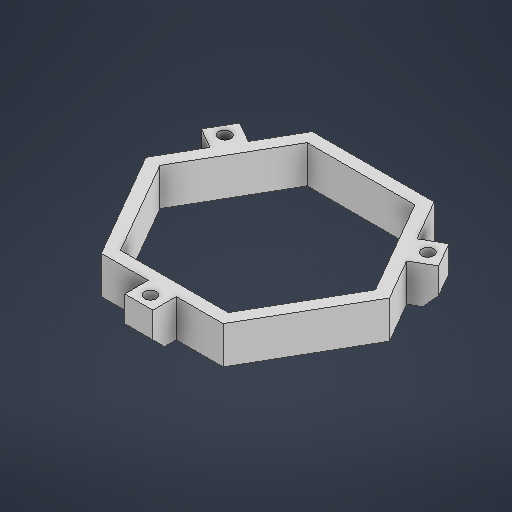
# Autodesk Inventor part: Gear Base
Saved by Autodesk Inventor 2026.3 (Build 303398000, 398)
## iProperties
Created: 2026-06-26
Part Number: Gear Base
Material: Generic
Document SubType Name: Modeling
Designer: joaqu
Density: 1 g/cm^3
Appearance: Default
Author: joaqu
Autodesk Inventor part; units mm, degrees
ref_plane "YZ Plane" through (0, 0, 0) normal (1, 0, 0) x (0, 1, 0)
ref_plane "XZ Plane" through (0, 0, 0) normal (0, 1, 0) x (-1, 0, 0)
ref_plane "XY Plane" through (0, 0, 0) normal (0, 0, 1) x (1, 0, 0)
sketch "Sketch1" plane through (0, 0, 0) normal (0, 1, 0) x (-1, 0, 0)
  line L0 (-115, 0) -> (-57.5, 99.5929)
  line L1 (-57.5, 99.5929) -> (57.5, 99.5929)
  line L2 (57.5, 99.5929) -> (115, 0)
  line L3 (115, 0) -> (57.5, -99.5929)
  line L4 (57.5, -99.5929) -> (-57.5, -99.5929)
  line L5 (-57.5, -99.5929) -> (-115, 0)
  line L6 (-130, 0) -> (-65, 112.5833)
  line L7 (-65, 112.5833) -> (65, 112.5833)
  line L8 (65, 112.5833) -> (130, 0)
  line L9 (130, 0) -> (65, -112.5833)
  line L10 (65, -112.5833) -> (-65, -112.5833)
  line L11 (-65, -112.5833) -> (-130, 0)
  point P0 (0, 0)
  point P1 (0, 0)
  point P2 (0, 0)
  dimension "d0" = 115
  dimension "d2" = 130
  constraints: 24 end point, 2 coincident, 26 other
  measures "d0" distance of L3.end L4.end
  measures "d2" distance of L9.end L10.end
extrude "Extrusion1" add sketch "Sketch1" along normal blind 40
sketch "Sketch3" plane through (-65, 0, 112.5833) normal (0, 0, 1) x (1, 0, 0)
  line L0 (130, 0) -> (0, 0) projected
  line L1 (130, 40) -> (0, 40) projected
  line L2 (50, 0) -> (80, 0)
  line L3 (80, 0) -> (80, 40)
  line L4 (80, 40) -> (50, 40)
  line L5 (50, 40) -> (50, 0)
  point P0 (65, 0)
  point P1 (65, 0)
  point P2 (65, 0)
  dimension "d5" = 15
  dimension "d6" = 15
  constraints: 8 end point, 2 midpoint, 2 parallel, 2 point on line, 1 horizontal, 1 perpendicular
  measures "d5" distance from line of L5 point (65, 0)
  measures "d6" distance from line of L3 point (65, 0)
extrude "Extrusion2" add sketch "Sketch3" along normal blind 25
chamfer "Chamfer1" distance 12.5 angle 45 1 edges at (0, 0, 137.5833)
sketch "Sketch4" plane through (-15, 12.5, 137.5833) normal (0, -0.7071, 0.7071) x (1, 0, 0)
  circle A0 centre (15, -8.8387) radius 6.375
  line L0 (0, 0) -> (0, -17.6777) projected
  line L1 (30, 0) -> (0, 0) projected
  line L2 (0, -17.6777) -> (30, -17.6777) projected
  point P0 (15, -106.1249)
  point P1 (15, 0)
  dimension "d16" = 8.839
  dimension "d25" = 12.75
  constraints: 1 centre point, 1 midpoint
  measures "d16" distance from line of L2 A0.centre
  measures "d25" diameter of A0
extrude "Extrusion3" cut sketch "Sketch4" against normal blind 15
pattern_circular "Circular Pattern1" count 3 over 360 about axis through (0, -10, 0) along (0, 1, 0) of "Extrusion2", "Chamfer1", "Extrusion3"
sketch "Sketch7" plane through (0, 40, 0) normal (0, 1, 0) x (1, 0, 0)
  line L0 (115.8253, 49.5513) -> (100.8253, 75.532) projected
  circle A0 centre (108.3253, 62.5417) radius 6.375
  point P0 (0, 0)
  dimension "d24" = 12.75
  constraints: 1 centre point, 1 midpoint
  measures "d24" diameter of A0
extrude "Extrusion4" cut sketch "Sketch7" against normal blind 10
pattern_circular "Circular Pattern2" count 3 over 360 about axis through (0, -10, 0) along (0, 1, 0) of "Extrusion4"
body "Solid1"
